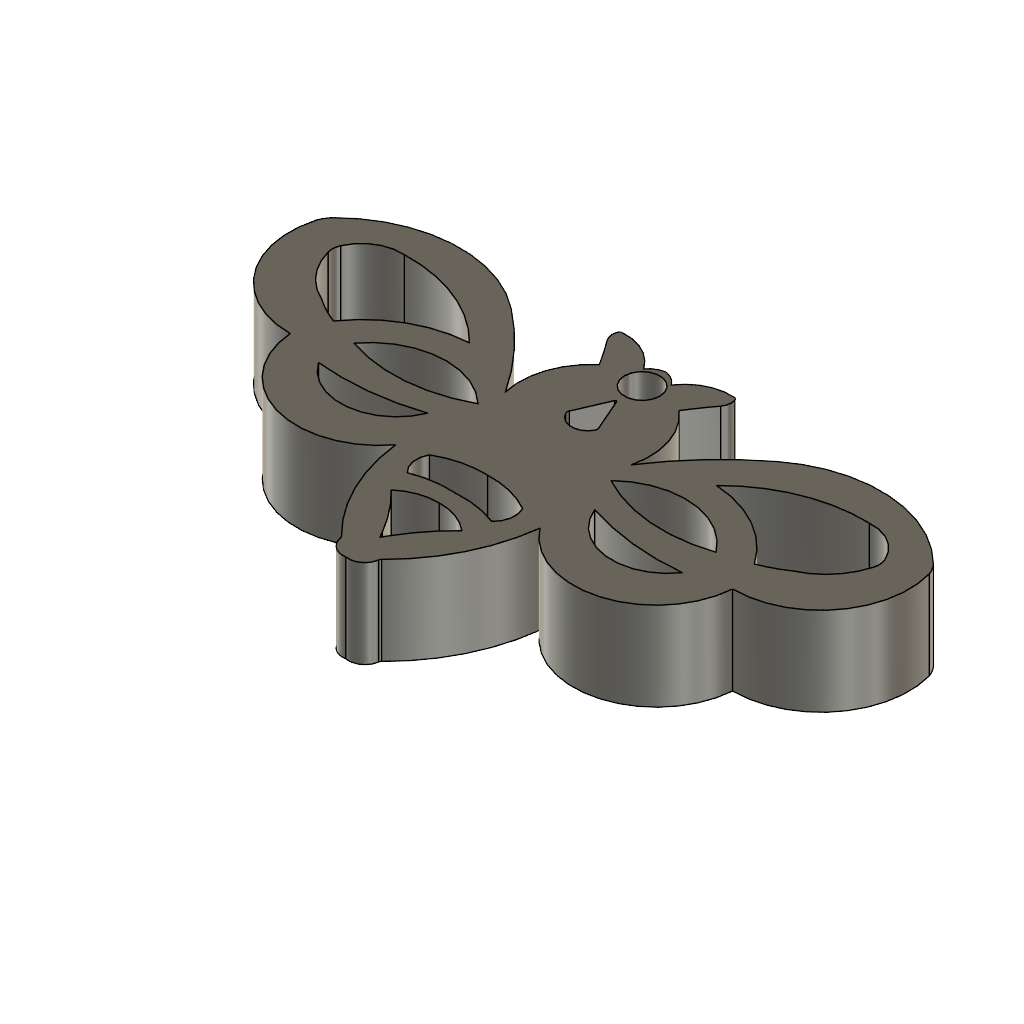
llavero-abeja (Autodesk Fusion 360 design; units mm, degrees)
part number: 2026-10-01-09-13-53-424
Autodesk Fusion 360 part; units mm, degrees
sketch "Boceto1" plane through (0, 0, 0) normal (0, 0, 1) x (1, 0, 0)
sketch "Boceto2" plane through (0, 0, 0) normal (0, 0, 1) x (1, 0, 0)
  arc A0 (-0.087, 0.0004) -> (1.3432, 0.3026) centre (-0.0288, 3.2602) ccw
  arc A1 (2.0573, -1.6109) -> (-0.087, -1.2265) centre (0.0573, -6.5953) ccw
  arc A2 (2.0573, -1.6109) -> (1.3432, 0.3026) centre (-0.0745, -1.3165) ccw
  arc A3 (2.0217, -2.5987) -> (-0.087, -2.0777) centre (0.0542, -6.0336) ccw
  arc A4 (1.8217, -3.7987) -> (-0.087, -3.5094) centre (0.2386, -7.8029) ccw
  arc A5 (1.8217, -3.7987) -> (2.0217, -2.5987) centre (1.1406, -3.0685) ccw
  arc A6 (1.5107, -4.8382) -> (0.0573, -6.6958) centre (7.3428, -10.8986) ccw
  arc A7 (1.5107, -4.8382) -> (-0.087, -4.2624) centre (-0.0304, -6.61) ccw
  arc A8 (0.8192, -7.7782) -> (3.1786, -2.9718) centre (-4.8499, -2.0129) ccw
  arc A9 (3.1786, -2.9718) -> (9.9217, -0.9987) centre (6.1725, -0.6946) ccw
  arc A10 (9.9217, -0.9987) -> (13.7784, 4.0456) centre (9.9364, 2.9865) ccw
  arc A11 (13.495, 4.5167) -> (5.9217, 5.0013) centre (9.4343, 0.4761) ccw
  arc A12 (5.9217, 5.0013) -> (2.767, 1.5853) centre (14.5967, -6.1746) ccw
  arc A13 (13.7784, 4.0456) -> (13.4272, 4.5837) centre (12.5477, 3.6261) ccw
  arc A14 (2.767, 1.5853) -> (1.7179, 4.7804) centre (-0.372, 2.3243) ccw
  arc A15 (2.4858, 5.8998) -> (1.7179, 4.7804) centre (15.7678, -4.0352) ccw
  arc A16 (2.4568, 6.556) -> (0.5434, 5.6139) centre (2.3021, 4.4561) ccw
  arc A17 (2.4858, 5.8998) -> (2.5796, 6.4495) centre (1.996, 6.2662) ccw
  arc A18 (2.5796, 6.4495) -> (2.4191, 6.5585) centre (2.4277, 6.3985) ccw
  arc A19 (0.5434, 5.6139) -> (-0.087, 6.0036) centre (-0.2297, 5.0681) ccw
  arc A20 (3.6913, -1.0064) -> (8.145, -1.4924) centre (7.0622, 9.2337) ccw
  arc A21 (3.6913, -1.0064) -> (8.145, -1.4924) centre (6.0492, -0.0489) ccw
  arc A22 (8.1033, 0.0699) -> (2.9217, 0.5013) centre (5.3228, -1.9934) ccw
  arc A23 (2.9217, 0.5013) -> (8.1033, 0.0699) centre (6.0045, 6.1961) ccw
  arc A24 (10.4322, 4.6767) -> (5.5052, 2.6969) centre (10.2289, -1.9378) ccw
  arc A25 (9.4343, 0.4761) -> (5.5052, 2.6969) centre (5.1772, -2.4695) ccw
  arc A26 (12.2213, 3.588) -> (10.4322, 4.6767) centre (10.5545, 2.8633) ccw
  arc A27 (12.2584, 3.056) -> (12.2677, 3.0905) centre (9.6802, 3.7721) ccw
  arc A28 (10.557, 1.063) -> (12.2677, 3.0905) centre (9.2721, 3.8825) ccw
  arc A29 (9.4343, 0.4761) -> (10.557, 1.063) centre (7.64, 5.2758) ccw
  arc A30 (12.2584, 3.056) -> (12.2213, 3.588) centre (11.4892, 3.2697) ccw
  arc A31 (-0.087, -8.4899) -> (0.7809, -7.849) centre (0.0425, -7.7572) ccw
  arc A32 (0.8192, -7.7782) -> (0.7785, -7.8661) centre (0.9153, -7.876) ccw
  line L0 (0.0573, -6.6958) -> (-0.087, -6.946)
  arc A33 (-1.5173, 0.3036) -> (-0.087, 0.0014) centre (-0.1453, 3.2613) ccw
  arc A34 (-1.5173, 0.3036) -> (-2.2313, -1.6098) centre (-0.0996, -1.3154) ccw
  arc A35 (-0.087, -1.2255) -> (-2.2313, -1.6098) centre (-0.2313, -6.5943) ccw
  arc A36 (-5.6793, 2.6969) -> (-10.6062, 4.6767) centre (-10.403, -1.9378) ccw
  arc A37 (-10.7311, 1.063) -> (-9.6084, 0.4761) centre (-7.8141, 5.2758) ccw
  arc A38 (-12.4418, 3.0905) -> (-10.7311, 1.063) centre (-9.4462, 3.8825) ccw
  arc A39 (-12.3954, 3.588) -> (-12.4325, 3.056) centre (-11.6633, 3.2697) ccw
  arc A40 (-10.6062, 4.6767) -> (-12.3954, 3.588) centre (-10.7285, 2.8633) ccw
  arc A41 (-5.6793, 2.6969) -> (-9.6084, 0.4761) centre (-5.3513, -2.4695) ccw
  arc A42 (-12.4418, 3.0905) -> (-12.4325, 3.056) centre (-9.8543, 3.7721) ccw
  arc A43 (-13.9525, 4.0456) -> (-10.0958, -0.9987) centre (-10.1105, 2.9865) ccw
  arc A44 (-6.0958, 5.0013) -> (-13.6691, 4.5167) centre (-9.6084, 0.4761) ccw
  arc A45 (-13.6013, 4.5837) -> (-13.9525, 4.0456) centre (-12.7218, 3.6261) ccw
  arc A46 (-2.9411, 1.5853) -> (-6.0958, 5.0013) centre (-14.7708, -6.1746) ccw
  arc A47 (-3.0958, 0.5013) -> (-8.2774, 0.0699) centre (-5.4969, -1.9934) ccw
  arc A48 (-8.2774, 0.0699) -> (-3.0958, 0.5013) centre (-6.1786, 6.1961) ccw
  arc A49 (-8.3191, -1.4924) -> (-3.8654, -1.0064) centre (-7.2363, 9.2337) ccw
  arc A50 (-8.3191, -1.4924) -> (-3.8654, -1.0064) centre (-6.2233, -0.0489) ccw
  arc A51 (-10.0958, -0.9987) -> (-3.3527, -2.9718) centre (-6.3466, -0.6946) ccw
  arc A52 (-1.8919, 4.7804) -> (-2.9411, 1.5853) centre (0.1979, 2.3243) ccw
  arc A53 (-1.8919, 4.7804) -> (-2.6599, 5.8998) centre (-15.9419, -4.0352) ccw
  arc A54 (-2.7537, 6.4495) -> (-2.6599, 5.8998) centre (-2.1701, 6.2662) ccw
  arc A55 (-2.5932, 6.5585) -> (-2.7537, 6.4495) centre (-2.6018, 6.3985) ccw
  arc A56 (-0.7175, 5.6139) -> (-2.6309, 6.556) centre (-2.4762, 4.4561) ccw
  arc A57 (-0.087, 6.0036) -> (-0.7175, 5.6139) centre (0.0556, 5.0681) ccw
  arc A58 (-2.1958, -2.5987) -> (-1.9958, -3.7987) centre (-1.3147, -3.0685) ccw
  arc A59 (-0.087, -2.0777) -> (-2.1958, -2.5987) centre (-0.2283, -6.0336) ccw
  arc A60 (-0.087, -3.5094) -> (-1.9958, -3.7987) centre (-0.4127, -7.8029) ccw
  arc A61 (-0.9526, -7.8661) -> (-0.9933, -7.7782) centre (-1.0894, -7.876) ccw
  arc A62 (-0.955, -7.849) -> (-0.087, -8.4899) centre (-0.2166, -7.7572) ccw
  arc A63 (-3.3527, -2.9718) -> (-0.9933, -7.7782) centre (4.6758, -2.0129) ccw
  arc A64 (-0.2313, -6.6958) -> (-1.6848, -4.8382) centre (-7.5169, -10.8986) ccw
  arc A65 (-0.087, -4.2624) -> (-1.6848, -4.8382) centre (-0.1436, -6.61) ccw
  line L1 (-0.2313, -6.6958) -> (-0.087, -6.946)
  arc A66 (-0.7384, 2.1095) -> (0.5811, 2.1083) centre (-0.0783, 2.4513) ccw
  line L2 (-0.7448, 2.28) -> (-0.1325, 3.7145)
  line L3 (0.5869, 2.2808) -> (-0.0407, 3.7149)
  arc A67 (-0.7448, 2.28) -> (-0.7384, 2.1095) centre (-0.5608, 2.2015) ccw
  arc A68 (-0.0407, 3.7149) -> (-0.1325, 3.7145) centre (-0.0865, 3.6949) ccw
  arc A69 (0.5811, 2.1083) -> (0.5869, 2.2808) centre (0.4037, 2.2006) ccw
  circle A70 centre (-0.0783, 4.9098) radius 0.8
  constraint coincident origin A0
  constraint tangent A11 A12
  constraint coincident A11 A13.end
  constraint coincident A13 A11.start
  constraint tangent A12 A15
  constraint tangent A12 A16
  constraint tangent A15 A17
  constraint coincident A16 A18.end
  constraint coincident A18 A16.start
  constraint coincident A11.centre A25.start
  constraint tangent A26 A30
  constraint tangent A27 A30
  constraint tangent A28 A30
  constraint tangent A8 A32
  constraint coincident A31 A32.end
  constraint coincident A32 A31.end
  constraint tangent A6 L0
  constraint tangent L2 A67
  constraint tangent A66 A67
  constraint tangent L2 A68
  constraint tangent L3 A68
  constraint tangent L3 A69
  constraint tangent A66 A69
extrude "Extruir1" add sketch "Boceto2" along normal blind 4 contours A0 A1 A2 A33 A34 A35 | A8 A9 A10 A11 A12 A13 A14 A15 A16 A17 A18 A19 A31 A32 A43 A44 A45 A46 A51 A52 A53 A54 A55 A56 A57 A61 A62 A63
